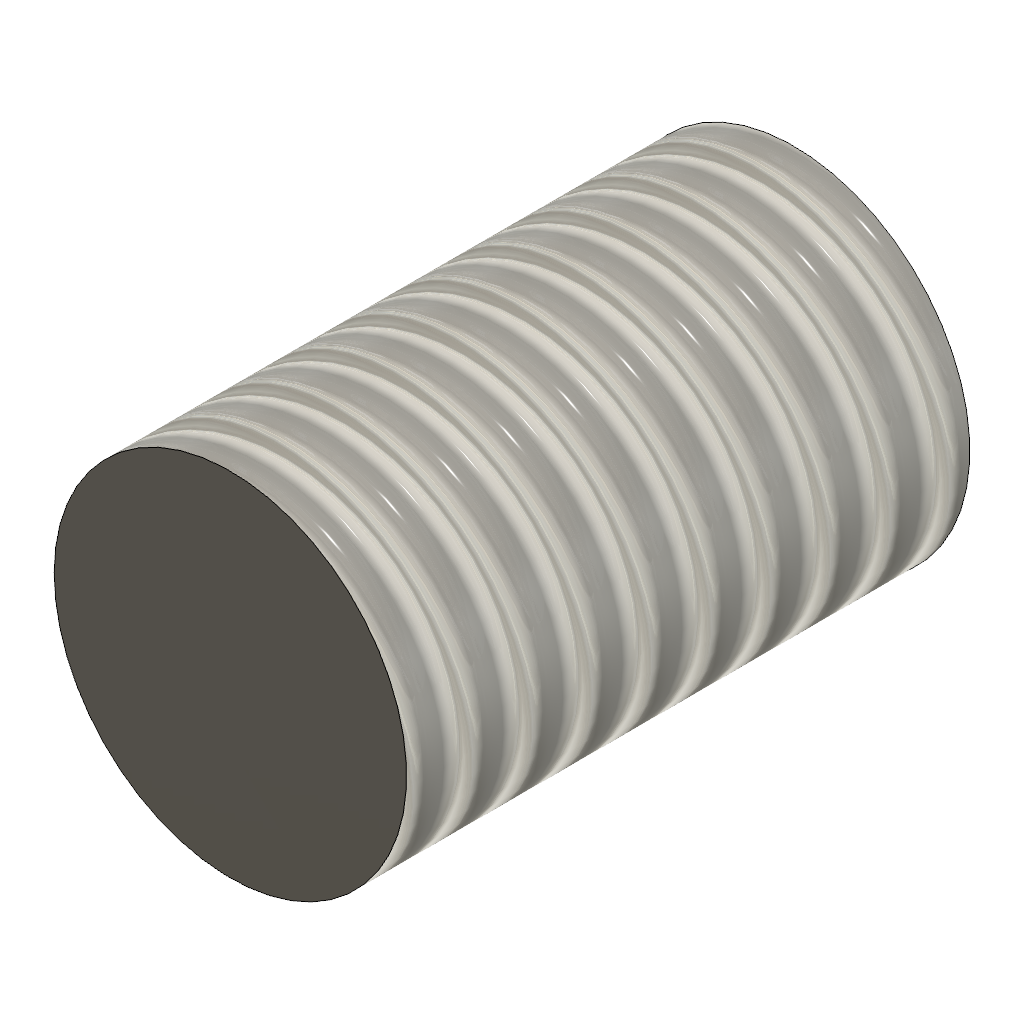
ansi_unified_external (Autodesk Fusion 360 design; units mm, degrees)
part number: 2026-10-21-16-02-13-621
Autodesk Fusion 360 part; units mm, degrees
sketch "OwnedThreadProfile_0_ansi_unified_external" plane through (0, 0, 0) normal (0, 0, 1) x (1, 0, 0)
  circle A0 centre (0, 0) radius 6
extrude "OwnedThreadCylinderExtrude_0_ansi_unified_external" add sketch "OwnedThreadProfile_0_ansi_unified_external" along normal blind 20
thread "OwnedThreadFamily_ansi_unified_external" "ANSI Unified Screw Threads 0.5 1/2-12 UNS 1/2-12 UNS 2A" major diameter 12.5146 minor diameter 10.1397 pitch 2.1167 angle 60 resizes the face on face at (5.9925, -0.2991, 13.3333)
named bodies: "OwnedThreadCylinder_0_ansi_unified_external"
